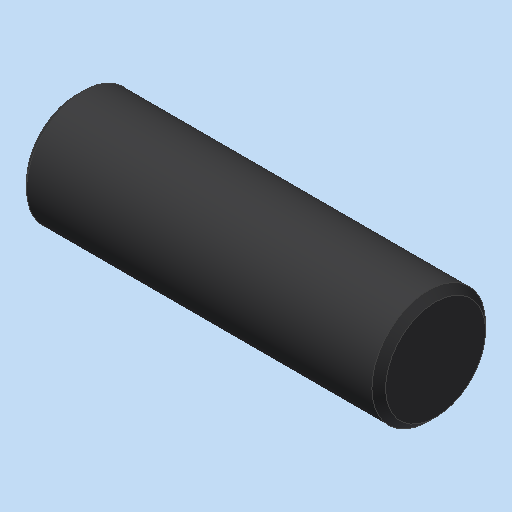
# Autodesk Inventor part: MM0861AN100_G01_117
Saved by Autodesk Inventor 2023.3 (Build 273359000, 359)
## iProperties
Created: 2018-10-30
Part Number: MM0861AN100_G01_117
Material: 1.2379 X155CrVMo 12-1
Document SubType Name: Modeling
Designer: Rose
Density: 7.85 g/cm^3
Appearance: Grün
Description: =<RBPARTNOTITLE2>
Mass: 2.42467 g
Surface Area: 2.81701 cm^2
Volume: 0.308875 cm^3
RBMATERIAL: =<Material>
RBMATNO: =<Part Number>
RBPARTMADEOF: Rd.6x21
RBPARTNOTITLE1: manufactured part
RBPARTNOTITLE2: Anfertigungsteil
MaxAbmaße: 0 x 0 x 0 (FM)
AnP_Material_aktuell: =<Material>
AnP_Kommentar_aktuell: =<Comments>
RBDRAWINGMISSINGSPEC: --
AnP_Kategorie: 1
AnP_Material: =<Material>
RBSURFACE2: HRC 60±2 DyLin beschichtet
Author: Rose
Keywords: =<RBPARTMADEOF>
Comments: =<RBSURFACE2>
Revision Number: 01
Autodesk Inventor part; units mm, degrees
ref_plane "YZ Plane" through (0, 0, 0) normal (1, 0, 0) x (0, 1, 0)
ref_plane "XZ Plane" through (0, 0, 0) normal (0, 1, 0) x (-1, 0, 0)
ref_plane "XY Plane" through (0, 0, 0) normal (0, 0, 1) x (1, 0, 0)
sketch "Skizze1" plane through (0, 0, 0) normal (0, 0, 1) x (1, 0, 0)
  line L0 (-11.06, 0) -> (11.06, 0) projected
  line L1 (7.9, 0) -> (7.9, 2.5)
  line L2 (7.9, 2.5) -> (-7.9, 2.5)
  line L3 (-7.9, 2.5) -> (-7.9, 0)
  line L4 (0, 3) -> (0, -0.5) projected
  dimension "d12" = 15.8
  dimension "d13" = 5
  constraints: 6 end point, 2 perpendicular, 2 point on line, 1 parallel, 1 other
  measures "d12" distance between parallel lines of L1 L3
  measures "d13" diameter of L2 L0
revolve "Umdrehung1" add sketch "Skizze1" angle 360 about axis through (0, 0, 0) along (1, 0, 0)
chamfer "Fase1" distance 0.3 angle 45 2 edges at (-7.9, -2.5, 0) (7.9, -2.5, 0)
